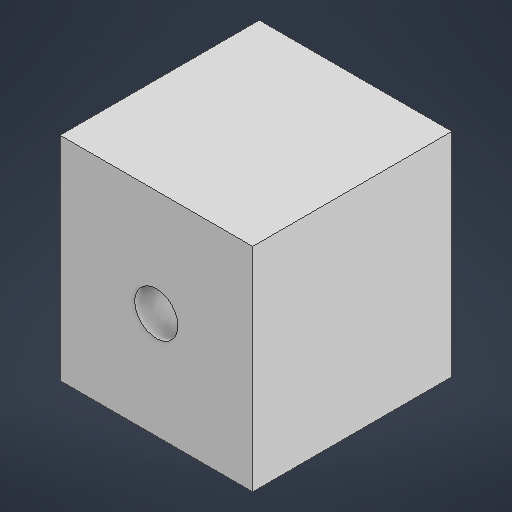
# Autodesk Inventor part: top_mount
Saved by Autodesk Inventor 2027 (Build 310192060, 192F)
## iProperties
Created: 2026-09-14
Part Number: top_mount
Material: Generic
Document SubType Name: Modeling
Designer: Aiden
Density: 1 g/cm^3
Appearance: Default
Author: Aiden
Autodesk Inventor part; units mm, degrees
ref_plane "YZ Plane" through (0, 0, 0) normal (1, 0, 0) x (0, 1, 0)
ref_plane "XZ Plane" through (0, 0, 0) normal (0, 1, 0) x (-1, 0, 0)
ref_plane "XY Plane" through (0, 0, 0) normal (0, 0, 1) x (1, 0, 0)
sketch "Sketch1" plane through (0, 0, 0) normal (0, 1, 0) x (-1, 0, 0)
  line L0 (0, 0) -> (7.366, 0)
  line L1 (7.366, 0) -> (7.366, -7.62)
  line L2 (7.366, -7.62) -> (0, -7.62)
  line L3 (0, -7.62) -> (0, 0)
  dimension "d0" = 7.366
  dimension "d1" = 7.62
  constraints: 8 end point, 2 parallel, 1 horizontal, 1 perpendicular
  measures "d0" distance of L0.start L0.end
  measures "d1" distance of L0.end L1.end
extrude "Extrusion1" add sketch "Sketch1" along normal blind 8.128
sketch "Sketch2" plane through (-7.366, 0, 0) normal (0, 0, 1) x (1, 0, 0)
  circle A0 centre (3.683, 4.064) radius 0.825
  line L0 (7.366, 8.128) -> (0, 8.128) construction
  line L1 (3.683, 8.128) -> (3.683, -0.0002) construction
  line L2 (0, 0) -> (0, 8.128) construction
  line L3 (7.366, 0) -> (7.366, 8.128) construction
  line L4 (7.366, 4.064) -> (0, 4.064) construction
  dimension "d4" = 1.65
  constraints: 4 end point, 4 midpoint, 2 coincident, 1 centre point, 1 perpendicular
  measures "d4" diameter of A0
extrude "Extrusion2" cut sketch "Sketch2" against normal blind 25.4
body "Solid1"
